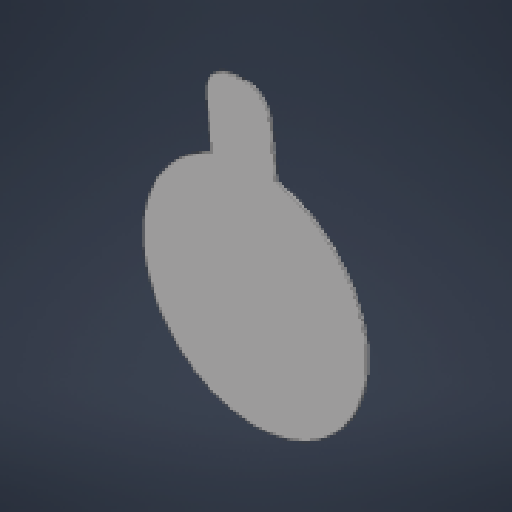
# Autodesk Inventor part: 背面贴纸
Saved by Autodesk Inventor 2025 (Build 290162000, 162)
## iProperties
Created: 2025-09-25
Part Number: 背面贴纸
Material: 常规
Document SubType Name: Modeling
Designer: HZD
Density: 1 g/cm^3
Appearance: 默认
Author: HZD
Autodesk Inventor part; units mm, degrees
ref_plane "YZ Plane" through (0, 0, 0) normal (1, 0, 0) x (0, 1, 0)
ref_plane "XZ Plane" through (0, 0, 0) normal (0, 1, 0) x (-1, 0, 0)
ref_plane "XY Plane" through (0, 0, 0) normal (0, 0, 1) x (1, 0, 0)
sketch "草图1" plane through (0, 0, 0) normal (0, 0, 1) x (1, 0, 0)
  circle A0 centre (0, 0) radius 29.5
  line L0 (3.9996, 41.9007) -> (5.4004, 29.0015) projected
  arc A1 (-11.5002, 27.1661) -> (5.4004, 29.0015) centre (0, 0) ccw projected
  line L1 (-11.5002, 27.1661) -> (-12.9011, 40.0653) projected
  arc A2 (-6.9193, 47.5046) -> (-12.9011, 40.0653) centre (-6.1905, 40.7941) ccw projected
  line L2 (-6.9193, 47.5046) -> (-3.4398, 47.8825) projected
  arc A3 (3.9996, 41.9007) -> (-3.4398, 47.8825) centre (-2.711, 41.172) ccw projected
  line L3 (3.5771, 27.2664) -> (2.5171, 22.8618) projected
  arc A4 (-7.3662, 21.7885) -> (2.5171, 22.8618) centre (0, 0) ccw projected
  line L4 (-7.3662, 21.7885) -> (-9.3469, 25.8628) projected
  arc A5 (-9.3469, 25.8628) -> (3.5771, 27.2664) centre (0, 0) ccw projected
  line L5 (-5.8421, 26.0083) -> (0.1228, 26.6561) projected
  line L6 (0.1228, 26.6561) -> (-1.6047, 42.5625) projected
  line L7 (-1.6047, 42.5625) -> (-7.5696, 41.9147) projected
  line L8 (-7.5696, 41.9147) -> (-5.8421, 26.0083) projected
  point P0 (-6.1509, 28.8516)
  point P1 (-0.186, 29.4994)
  dimension "d0" = 59
  constraints: 1 centre point, 1 coincident
  measures "d0" diameter of A0
extrude "拉伸1" add sketch "草图1" along normal blind 0.5 contours A0 L8 L5 L6 | A0 L6 L7 L8 L1 A2 L2 A3 L0 | L6 L5 L8 A0 | A0 L8 L7 L6 | A5 L4 A4 L3
